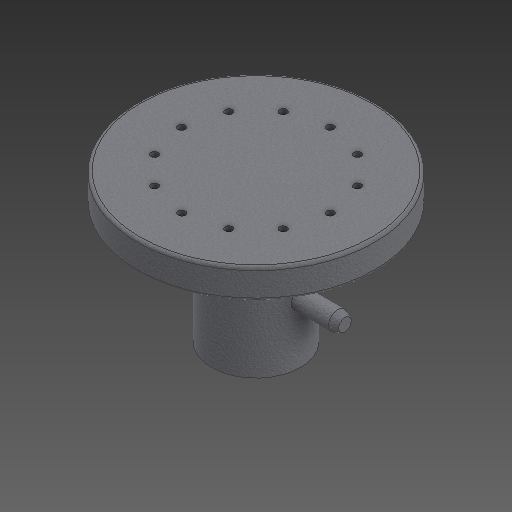
# Autodesk Inventor part: Friday28aug
Saved by Autodesk Inventor 2026.1 (Build 301233020, 233B)
## iProperties
Created: 2026-08-28
Part Number: Friday28aug
Material: Generic
Document SubType Name: Modeling
Designer: YmCris
Density: 1 g/cm^3
Appearance: Default
Author: YmCris
Autodesk Inventor part; units mm, degrees
ref_plane "XZ Plane" through (0, 0, 0) normal (0, 1, 0) x (-1, 0, 0)
ref_plane "XY Plane" through (0, 0, 0) normal (0, 0, 1) x (1, 0, 0)
sketch "Sketch1" plane through (0, 0, 0) normal (0, 0, 1) x (1, 0, 0)
  line L0 (0, 0) -> (30, 0)
  line L1 (30, 0) -> (30, 78)
  line L2 (0, 80) -> (0, 0)
  line L3 (32, 80) -> (78, 80)
  line L4 (80, 82) -> (80, 98)
  line L5 (78, 100) -> (0, 100)
  line L6 (0, 100) -> (0, 80)
  arc A0 (80, 98) -> (78, 100) centre (78, 98) ccw
  arc A1 (78, 80) -> (80, 82) centre (78, 82) ccw
  arc A2 (32, 80) -> (30, 78) centre (32, 78) ccw
  constraints: 14 end point, 6 point on circle, 6 tangent, 3 centre point, 3 parallel, 2 equal radius, 2 horizontal, 2 perpendicular, 1 coincident, 1 point on line
revolve "Revolution1" add sketch "Sketch1" angle 360 about axis through (0, 80, 0) along (0, -1, 0)
sketch "Sketch2" plane through (0, 0, 0) normal (0, -1, 0) x (1, 0, 0)
  point P0 (0, 0)
  point P1 (-0.0515, -0.0844)
hole "Hole1" at (-0.0515, 0, -0.0844) direction (0, 1, 0) diameter 48 depth 78.25 tip angle 118
sketch "Sketch4" plane through (0, 100, 0) normal (0, 1, 0) x (1, 0, 0)
  line L0 (0, 0) -> (-50, 0) construction
  circle A0 centre (-50, 0) radius 2.5
  circle A1 centre (-43.3013, -25) radius 2.5
  circle A2 centre (-25, -43.3013) radius 2.5
  circle A3 centre (0, -50) radius 2.5
  circle A4 centre (25, -43.3013) radius 2.5
  circle A5 centre (43.3013, -25) radius 2.5
  circle A6 centre (50, 0) radius 2.5
  circle A7 centre (43.3013, 25) radius 2.5
  circle A8 centre (25, 43.3013) radius 2.5
  circle A9 centre (0, 50) radius 2.5
  circle A10 centre (-25, 43.3013) radius 2.5
  circle A11 centre (-43.3013, 25) radius 2.5
  dimension "d20" = 50
  dimension "d21" = 5
  dimension "d24" = 360
  constraints: 12 centre point, 2 end point, 1 coincident, 1 horizontal, 25 other
  measures "d20" distance of L0.start L0.end
  measures "d21" diameter of A0
extrude "Extrusion1" cut sketch "Sketch4" against normal blind 4
ref_plane "Work Plane1" through (30, 0, 0) normal (1, 0, 0) x (0, 1, 0)
sketch "Sketch5" plane through (30, 0, 0) normal (1, 0, 0) x (0, 1, 0)
  line L0 (0, 0) -> (40, 0) construction
  circle A0 centre (40, 0) radius 6.25
  dimension "d29" = 40
  dimension "d30" = 12.5
  constraints: 2 end point, 1 centre point, 1 coincident, 1 horizontal
  measures "d29" distance of L0.start L0.end
  measures "d30" diameter of A0
extrude "Extrusion2" add sketch "Sketch5" along normal blind 30
chamfer "Chamfer1" distance 2 distance2 5 1 edges at (60, 33.75, 0) measured on face at (60, 38.3334, -0.4986)
body "Solid1"
